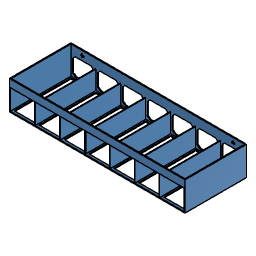
Small_Holder_PRINT (Autodesk Fusion 360 design; units mm, degrees)
Autodesk Fusion 360 part; units mm, degrees
sketch "Sketch1" plane through (0, 0, 0) normal (0, 0, 1) x (1, 0, 0)
  line L0 (0, 0) -> (232.6, 0)
  line L1 (232.6, 0) -> (232.6, 81.6)
  line L2 (232.6, 81.6) -> (0, 81.6)
  line L3 (0, 81.6) -> (0, 0)
  line L4 (1.2, 80.4) -> (231.4, 80.4)
  line L5 (231.4, 80.4) -> (231.4, 1.2)
  line L6 (231.4, 1.2) -> (1.2, 1.2)
  line L7 (1.2, 1.2) -> (1.2, 80.4)
  line L8 (3.2, 78.4) -> (31.4, 78.4)
  line L9 (31.4, 78.4) -> (31.4, 3.2)
  line L10 (31.4, 3.2) -> (3.2, 3.2)
  line L11 (3.2, 3.2) -> (3.2, 78.4)
  line L12 (33.4, 80.4) -> (34.2, 80.4)
  line L13 (34.2, 80.4) -> (34.2, 1.2)
  line L14 (34.2, 1.2) -> (33.4, 1.2)
  line L15 (33.4, 1.2) -> (33.4, 80.4)
  line L16 (36.2, 78.4) -> (64.4, 78.4)
  line L17 (36.2, 3.2) -> (36.2, 78.4)
  line L18 (64.4, 78.4) -> (64.4, 3.2)
  line L19 (64.4, 3.2) -> (36.2, 3.2)
  line L20 (69.2, 78.4) -> (97.4, 78.4)
  line L21 (69.2, 3.2) -> (69.2, 78.4)
  line L22 (97.4, 78.4) -> (97.4, 3.2)
  line L23 (97.4, 3.2) -> (69.2, 3.2)
  line L24 (102.2, 78.4) -> (130.4, 78.4)
  line L25 (102.2, 3.2) -> (102.2, 78.4)
  line L26 (130.4, 78.4) -> (130.4, 3.2)
  line L27 (130.4, 3.2) -> (102.2, 3.2)
  line L28 (135.2, 78.4) -> (163.4, 78.4)
  line L29 (135.2, 3.2) -> (135.2, 78.4)
  line L30 (163.4, 78.4) -> (163.4, 3.2)
  line L31 (163.4, 3.2) -> (135.2, 3.2)
  line L32 (168.2, 78.4) -> (196.4, 78.4)
  line L33 (168.2, 3.2) -> (168.2, 78.4)
  line L34 (196.4, 78.4) -> (196.4, 3.2)
  line L35 (196.4, 3.2) -> (168.2, 3.2)
  line L36 (66.4, 80.4) -> (67.2, 80.4)
  line L37 (67.2, 80.4) -> (67.2, 1.2)
  line L38 (67.2, 1.2) -> (66.4, 1.2)
  line L39 (66.4, 1.2) -> (66.4, 80.4)
  line L40 (99.4, 80.4) -> (100.2, 80.4)
  line L41 (100.2, 80.4) -> (100.2, 1.2032)
  line L42 (100.2, 1.2032) -> (99.4, 1.2032)
  line L43 (99.4, 1.2032) -> (99.4, 80.4)
  line L44 (132.4, 80.4) -> (133.2, 80.4)
  line L45 (133.2, 80.4) -> (133.2, 1.2)
  line L46 (133.2, 1.2) -> (132.4, 1.2)
  line L47 (132.4, 1.2) -> (132.4, 80.4)
  line L48 (165.4, 80.4) -> (166.2, 80.4)
  line L49 (166.2, 80.4) -> (166.2, 1.2)
  line L50 (166.2, 1.2) -> (165.4, 1.2)
  line L51 (165.4, 1.2) -> (165.4, 80.4)
  line L52 (198.4, 80.4) -> (199.2, 80.4)
  line L53 (199.2, 80.4) -> (199.2, 1.2)
  line L54 (199.2, 1.2) -> (198.4, 1.2)
  line L55 (198.4, 1.2) -> (198.4, 80.4)
  line L56 (201.2, 78.4) -> (229.4, 78.4)
  line L57 (201.2, 3.2) -> (201.2, 78.4)
  line L58 (229.4, 3.2) -> (201.2, 3.2)
  line L59 (229.4, 78.4) -> (229.4, 3.2)
  line L60 (231.4, 80.4) -> (232.2, 80.4)
  line L61 (232.2, 1.2) -> (231.4, 1.2)
  dimension "d1" = 1.2
  dimension "d2" = 1.2
  dimension "d3" = 1.2
  dimension "d4" = 1.2
  dimension "d5" = 2
  dimension "d6" = 2
  dimension "d7" = 2
  dimension "d8" = 81.6
  dimension "d9" = 0.8
  dimension "d10" = 2
  dimension "d11" = 32.2
  dimension "d12" = 0.8
  dimension "d13" = 0.8
  dimension "d14" = 0.8
  dimension "d15" = 0.8
  dimension "d16" = 2
  dimension "d17" = 0
  dimension "d19" = 2
  dimension "d21" = 32.2
  dimension "d22" = 2
  dimension "d23" = 2
  dimension "d24" = 32.2
  dimension "d25" = 2
  dimension "d26" = 2
  dimension "d27" = 32.2
  dimension "d28" = 2
  dimension "d29" = 2
  dimension "d30" = 32.2
  dimension "d31" = 2
  dimension "d32" = 0.8
  dimension "d33" = 2
  dimension "d34" = 32.2
  dimension "d35" = 2
  dimension "d36" = 2
  dimension "d38" = 2
  dimension "d39" = 2
  dimension "d40" = 2
  dimension "d41" = 2
  dimension "d43" = 2
  dimension "d47" = 2
  dimension "d48" = 2
  dimension "d49" = 2
  dimension "d50" = 2
  dimension "d51" = 2
  dimension "d52" = 2
  dimension "d53" = 32.2
  dimension "d54" = 1.2
  dimension "d306" = 0
  dimension "d307" = 0
  dimension "d308" = 0
  dimension "d309" = 0
  constraint horizontal L0
  constraint vertical L1
  constraint horizontal L2
  constraint vertical L3
  constraint coincident L0.start L3.end
  constraint horizontal L4
  constraint vertical L5
  constraint horizontal L6
  constraint vertical L7
  constraint horizontal L8
  constraint vertical L9
  constraint horizontal L10
  constraint vertical L11
  constraint horizontal L12
  constraint vertical L13
  constraint horizontal L14
  constraint vertical L15
  constraint coincident L6 L13.end
  constraint coincident L4 L12.start
  constraint horizontal L16
  constraint vertical L18
  constraint horizontal L19
  constraint vertical L17
  constraint horizontal L20
  constraint vertical L22
  constraint horizontal L23
  constraint vertical L21
  constraint horizontal L24
  constraint vertical L26
  constraint horizontal L27
  constraint vertical L25
  constraint horizontal L28
  constraint vertical L30
  constraint horizontal L31
  constraint vertical L29
  constraint horizontal L32
  constraint vertical L34
  constraint horizontal L35
  constraint vertical L33
  constraint horizontal L36
  constraint vertical L37
  constraint horizontal L38
  constraint vertical L39
  constraint coincident L4 L36.start
  constraint horizontal L40
  constraint vertical L41
  constraint horizontal L42
  constraint vertical L43
  constraint coincident L4 L40.start
  constraint horizontal L44
  constraint vertical L45
  constraint horizontal L46
  constraint vertical L47
  constraint coincident L4 L44.start
  constraint horizontal L48
  constraint vertical L49
  constraint horizontal L50
  constraint vertical L51
  constraint coincident L4 L48.start
  constraint horizontal L52
  constraint vertical L53
  constraint horizontal L54
  constraint vertical L55
  constraint coincident L4 L52.start
  constraint horizontal L56
  constraint vertical L59
  constraint horizontal L58
  constraint vertical L57
  constraint horizontal L60
  constraint horizontal L61
  constraint coincident L4 L5.start
  measures "d1" distance of L3 L7
  measures "d2" distance of L2 L4
  measures "d3" distance of L0 L6
  measures "d4" distance of L1 L5
  measures "d5" distance of L7 L11
  measures "d6" distance of L6 L10
  measures "d7" distance of L4 L8
  measures "d8" distance of L0.start L2.end
  measures "d9" distance of L13.end L14.end
  measures "d10" distance of L9 L15
  measures "d11" distance of L7 L15
  measures "d12" distance of L36.start L36.end
  measures "d13" distance of L40.start L40.end
  measures "d14" distance of L44.start L44.end
  measures "d15" distance of L48.start L48.end
  measures "d16" distance of L13 L17
  measures "d17" distance of L10 L19
  measures "d19" distance of L18 L39
  measures "d21" distance of L13 L39
  measures "d22" distance of L21 L37
  measures "d23" distance of L22 L43
  measures "d24" distance of L37 L43
  measures "d25" distance of L25 L41
  measures "d26" distance of L26 L47
  measures "d27" distance of L41 L47
  measures "d28" distance of L29 L45
  measures "d29" distance of L30 L51
  measures "d30" distance of L45 L51
  measures "d31" distance of L33 L49
  measures "d32" distance of L52.start L52.end
  measures "d33" distance of L34 L55
  measures "d34" distance of L49 L55
  measures "d35" distance of L4 L16
  measures "d36" distance of L4 L20
  measures "d38" distance of L4 L24
  measures "d39" distance of L4 L28
  measures "d40" distance of L4 L32
  measures "d41" distance of L53 L57
  measures "d43" distance of L4 L56
  measures "d47" distance of L6 L58
  measures "d48" distance of L6 L35
  measures "d49" distance of L6 L31
  measures "d50" distance of L6 L27
  measures "d51" distance of L6 L23
  measures "d52" distance of L5 L59
  measures "d53" distance of L5 L53
  measures "d54" distance of L2 L4
extrude "Extrude2" add sketch "Sketch1" along normal blind 38.2 contours L0 L1 L2 L3
extrude "Extrude1" add sketch "Sketch1" along normal blind 38 contours L4 L6 L7 L15 | L4 L6 L12 L13 L14 L15 | L4 L6 L13 L39 | L4 L6 L36 L37 L38 L39 | L4 L6 L37 L41 L42 L43 L47 | L4 L40 L41 L42 L43 | L4 L6 L44 L45 L46 L47 | L4 L6 L45 L51 | L4 L6 L48 L49 L50 L51 | L4 L6 L49 L55 | L4 L6 L52 L53 L54 L55 | L4 L5 L6 L53 | L8 L9 L10 L11 | L16 L17 L18 L19 | L20 L21 L22 L23 | L24 L25 L26 L27 | L28 L29 L30 L31 | L32 L33 L34 L35 | L56 L57 L58 L59
extrude "Extrude3" cut sketch "Sketch1" along normal blind 38 contours L8 L9 L10 L11 | L16 L17 L18 L19 | L20 L21 L22 L23 | L24 L25 L26 L27 | L28 L29 L30 L31 | L32 L33 L34 L35 | L56 L57 L58 L59
extrude "Extrude4" cut sketch "Sketch1" against normal blind 36.8 from surface at 38 contours L4 L6 L7 L15 | L4 L6 L13 L39 | L4 L6 L37 L41 L42 L43 L47 | L4 L6 L45 L51 | L4 L6 L49 L55 | L4 L5 L6 L53
sketch "Sketch2" plane through (0, 0, 0) normal (0, -1, 0) x (1, 0, 0)
  line L0 (0, 0) -> (232.6, 0)
  line L1 (232.6, 0) -> (232.6, 38.2)
  line L2 (232.6, 38.2) -> (0, 38.2)
  line L3 (0, 38.2) -> (0, 0)
  line L4 (1.2, 28.2) -> (33.4, 28.2)
  line L5 (33.4, 28.2) -> (33.4, 1.2)
  line L6 (33.4, 1.2) -> (1.2, 1.2)
  line L7 (1.2, 1.2) -> (1.2, 28.2)
  line L8 (34.2, 28.2) -> (66.4, 28.2)
  line L9 (66.4, 28.2) -> (66.4, 1.2)
  line L10 (66.4, 1.2) -> (34.2, 1.2)
  line L11 (34.2, 1.2) -> (34.2, 28.2)
  line L12 (67.2, 28.2) -> (99.4, 28.2)
  line L13 (99.4, 28.2) -> (99.4, 1.2)
  line L14 (99.4, 1.2) -> (67.2, 1.2)
  line L15 (67.2, 1.2) -> (67.2, 28.2)
  line L16 (100.2, 28.2) -> (132.4, 28.2)
  line L17 (132.4, 28.2) -> (132.4, 1.2)
  line L18 (132.4, 1.2) -> (100.2, 1.2)
  line L19 (100.2, 1.2) -> (100.2, 28.2)
  line L20 (133.2, 28.2) -> (165.4, 28.2)
  line L21 (165.4, 28.2) -> (165.4, 1.2)
  line L22 (165.4, 1.2) -> (133.2, 1.2)
  line L23 (133.2, 1.2) -> (133.2, 28.2)
  line L24 (1.2, 1.2) -> (1.2, 38.2)
  line L25 (166.2, 28.2) -> (198.4, 28.2)
  line L26 (166.2, 1.2) -> (166.2, 28.2)
  line L27 (198.4, 1.2) -> (166.2, 1.2)
  line L28 (198.4, 28.2) -> (198.4, 1.2)
  line L29 (199.2, 28.2) -> (231.4, 28.2)
  line L30 (199.2, 1.2) -> (199.2, 28.2)
  line L31 (231.4, 1.2) -> (199.2, 1.2)
  line L32 (231.4, 28.2) -> (231.4, 1.2)
  dimension "d65" = 32.2
  dimension "d66" = 0.8
  dimension "d67" = 32.2
  dimension "d68" = 0.8
  dimension "d69" = 32.2
  dimension "d70" = 0.8
  dimension "d71" = 32.2
  dimension "d72" = 0.8
  dimension "d73" = 32.2
  dimension "d74" = 32.2
  dimension "d75" = 32.2
  dimension "d77" = 0.8
  dimension "d78" = 0.8
  dimension "d79" = 1.2
  dimension "d80" = 27
  dimension "d81" = 27
  dimension "d82" = 27
  dimension "d83" = 10
  dimension "d84" = 10
  dimension "d85" = 10
  dimension "d86" = 10
  dimension "d87" = 10
  dimension "d88" = 10
  dimension "d89" = 10
  dimension "d90" = 9.8
  dimension "d91" = 27
  dimension "d92" = 27
  dimension "d93" = 27
  dimension "d94" = 27
  constraint horizontal L4
  constraint vertical L5
  constraint horizontal L6
  constraint vertical L7
  constraint horizontal L8
  constraint vertical L9
  constraint horizontal L10
  constraint vertical L11
  constraint horizontal L12
  constraint vertical L13
  constraint horizontal L14
  constraint vertical L15
  constraint horizontal L16
  constraint vertical L17
  constraint horizontal L18
  constraint vertical L19
  constraint horizontal L20
  constraint vertical L21
  constraint horizontal L22
  constraint vertical L23
  constraint collinear L7 L24
  constraint horizontal L25
  constraint vertical L28
  constraint horizontal L27
  constraint vertical L26
  constraint horizontal L29
  constraint vertical L32
  constraint horizontal L31
  constraint vertical L30
  measures "d65" distance of L4.start L4.end
  measures "d66" distance of L5 L11
  measures "d67" distance of L9.end L10.end
  measures "d68" distance of L9 L15
  measures "d69" distance of L13.end L14.end
  measures "d70" distance of L13 L19
  measures "d71" distance of L17.end L18.end
  measures "d72" distance of L17 L23
  measures "d73" distance of L21.end L22.end
  measures "d74" distance of L26.start L27.start
  measures "d75" distance of L30.start L31.start
  measures "d77" distance of L21 L26
  measures "d78" distance of L28 L30
  measures "d79" distance of L1 L32
  measures "d80" distance of L4.start L6.end
  measures "d81" distance of L8.start L10.end
  measures "d82" distance of L12.start L14.end
  measures "d83" distance of L2 L4
  measures "d84" distance of L2 L8
  measures "d85" distance of L2 L12
  measures "d86" distance of L2 L16
  measures "d87" distance of L2 L20
  measures "d88" distance of L2 L25
  measures "d89" distance of L2 L29
  measures "d91" distance of L29.end L31.start
  measures "d92" distance of L25.end L27.start
  measures "d93" distance of L20.end L21.end
  measures "d94" distance of L16.end L17.end
extrude "Extrude5" cut sketch "Sketch2" against normal blind 1.2 contours L4 L5 L6 L7 L24 | L8 L9 L10 L11 | L12 L13 L14 L15 | L16 L17 L18 L19 | L20 L21 L22 L23 | L25 L26 L27 L28 | L29 L30 L31 L32
sketch "Sketch3" plane through (0, 80.4, 0) normal (0, -1, 0) x (1, 0, 0)
  line L0 (231.4, 1.2) -> (231.4, 38.2)
  line L1 (231.4, 38.2) -> (1.2, 38.2)
  line L2 (1.2, 38.2) -> (1.2, 1.2)
  line L3 (3.2, 6.3232) -> (7.1045, 3.2)
  line L4 (7.1045, 3.2) -> (27.8654, 3.2)
  line L5 (27.8654, 3.2) -> (31.4, 6.7364)
  line L6 (31.4, 22.6654) -> (31.4, 6.7364)
  line L7 (31.4, 22.6654) -> (27.8636, 26.2)
  line L8 (6.7346, 26.2) -> (27.8636, 26.2)
  line L9 (6.7346, 26.2) -> (3.2, 22.6636)
  line L10 (3.2, 22.6636) -> (3.2, 6.3232)
  line L11 (1.2, 28.2) -> (33.4, 28.2)
  line L12 (33.4, 28.2) -> (33.4, 1.2)
  line L13 (33.4, 1.2) -> (1.2, 1.2)
  line L14 (39.7352, 26.2) -> (60.8766, 26.2)
  line L15 (36.2, 22.6641) -> (36.2, 6.3232)
  line L16 (39.7352, 26.2) -> (36.2, 22.6641)
  line L17 (36.2, 6.3232) -> (40.1046, 3.2)
  line L18 (40.1046, 3.2) -> (60.8772, 3.2)
  line L19 (60.8772, 3.2) -> (64.4124, 6.7359)
  line L20 (64.4124, 22.6648) -> (64.4124, 6.7359)
  line L21 (64.4124, 22.6648) -> (60.8766, 26.2)
  line L22 (72.7347, 26.2) -> (93.8636, 26.2)
  line L23 (69.2, 22.6636) -> (69.2, 6.3232)
  line L24 (72.7347, 26.2) -> (69.2, 22.6636)
  line L25 (69.2, 6.3232) -> (73.1046, 3.2)
  line L26 (73.1046, 3.2) -> (93.8653, 3.2)
  line L27 (93.8653, 3.2) -> (97.4, 6.7364)
  line L28 (97.4, 22.6653) -> (97.4, 6.7364)
  line L29 (97.4, 22.6653) -> (93.8636, 26.2)
  line L30 (105.7347, 26.2) -> (126.8636, 26.2)
  line L31 (102.2, 22.6636) -> (102.2, 6.3232)
  line L32 (105.7347, 26.2) -> (102.2, 22.6636)
  line L33 (102.2, 6.3232) -> (106.1046, 3.2)
  line L34 (106.1046, 3.2) -> (126.8653, 3.2)
  line L35 (126.8653, 3.2) -> (130.4, 6.7364)
  line L36 (130.4, 22.6653) -> (130.4, 6.7364)
  line L37 (130.4, 22.6653) -> (126.8636, 26.2)
  line L38 (138.7347, 26.2) -> (159.8636, 26.2)
  line L39 (135.2, 22.6636) -> (135.2, 6.3232)
  line L40 (138.7347, 26.2) -> (135.2, 22.6636)
  line L41 (135.2, 6.3232) -> (139.1046, 3.2)
  line L42 (139.1046, 3.2) -> (159.8653, 3.2)
  line L43 (159.8653, 3.2) -> (163.4, 6.7364)
  line L44 (163.4, 22.6653) -> (163.4, 6.7364)
  line L45 (163.4, 22.6653) -> (159.8636, 26.2)
  line L46 (204.7347, 26.2) -> (225.8636, 26.2)
  line L47 (201.2, 22.6636) -> (201.2, 6.3232)
  line L48 (204.7347, 26.2) -> (201.2, 22.6636)
  line L49 (201.2, 6.3232) -> (205.1046, 3.2)
  line L50 (205.1046, 3.2) -> (225.8653, 3.2)
  line L51 (225.8653, 3.2) -> (229.4, 6.7364)
  line L52 (229.4, 22.6653) -> (229.4, 6.7364)
  line L53 (229.4, 22.6653) -> (225.8636, 26.2)
  line L54 (199.2, 1.2) -> (199.2, 28.2)
  line L55 (199.2, 28.2) -> (231.4, 28.2)
  line L56 (231.4, 1.2) -> (199.2, 1.2)
  line L57 (198.4, 28.2) -> (198.4, 1.2)
  line L58 (133.2, 28.2) -> (165.4, 28.2)
  line L59 (165.4, 28.2) -> (165.4, 1.2)
  line L60 (165.4, 1.2) -> (133.2, 1.2)
  line L61 (133.2, 1.2) -> (133.2, 28.2)
  line L62 (132.4, 28.2) -> (132.4, 1.2)
  line L63 (132.4, 1.2) -> (100.2, 1.2)
  line L64 (100.2, 28.2) -> (132.4, 28.2)
  line L65 (100.2, 1.2) -> (100.2, 28.2)
  line L66 (67.2, 28.2) -> (99.4, 28.2)
  line L67 (99.4, 28.2) -> (99.4, 1.2)
  line L68 (99.4, 1.2) -> (67.2, 1.2)
  line L69 (67.2, 1.2) -> (67.2, 28.2)
  line L70 (34.2, 28.2) -> (66.4, 28.2)
  line L71 (34.2, 1.2) -> (34.2, 28.2)
  line L72 (66.4, 1.2) -> (34.2, 1.2)
  line L73 (171.7347, 26.2) -> (192.8636, 26.2)
  line L74 (168.2, 22.6636) -> (168.2, 6.3232)
  line L75 (171.7347, 26.2) -> (168.2, 22.6636)
  line L76 (168.2, 6.3232) -> (172.1046, 3.2)
  line L77 (172.1046, 3.2) -> (192.8653, 3.2)
  line L78 (192.8653, 3.2) -> (196.4, 6.7364)
  line L79 (196.4, 22.6653) -> (196.4, 6.7364)
  line L80 (196.4, 22.6653) -> (192.8636, 26.2)
  line L81 (166.2, 1.2) -> (166.2, 28.2)
  line L82 (198.4, 1.2) -> (166.2, 1.2)
  line L83 (166.2, 28.2) -> (198.4, 28.2)
  line L84 (33.4, 38) -> (34.2, 38)
  line L85 (34.2, 38) -> (34.2, 1.2)
  line L86 (34.2, 1.2) -> (66.4, 1.2)
  line L87 (66.4, 1.2) -> (66.4, 38)
  line L88 (66.4, 38) -> (67.2, 38)
  line L89 (67.2, 38) -> (67.2, 1.2)
  line L90 (67.2, 1.2) -> (99.4, 1.2)
  line L91 (99.4, 1.2) -> (99.4, 38)
  line L92 (99.4, 38) -> (100.2, 38)
  line L93 (100.2, 38) -> (100.2, 1.2)
  line L94 (100.2, 1.2) -> (132.4, 1.2)
  line L95 (132.4, 1.2) -> (132.4, 38)
  line L96 (132.4, 38) -> (133.2, 38)
  line L97 (133.2, 38) -> (133.2, 1.2)
  line L98 (133.2, 1.2) -> (165.4, 1.2)
  line L99 (165.4, 1.2) -> (165.4, 38)
  line L100 (165.4, 38) -> (166.2, 38)
  line L101 (166.2, 38) -> (166.2, 1.2)
  line L102 (166.2, 1.2) -> (198.4, 1.2)
  line L103 (198.4, 1.2) -> (198.4, 38)
  line L104 (198.4, 38) -> (199.2, 38)
  line L105 (199.2, 38) -> (199.2, 1.2)
  line L106 (199.2, 1.2) -> (231.4, 1.2)
  line L107 (1.2, 1.2) -> (33.4, 1.2)
  line L108 (33.4, 1.2) -> (33.4, 38)
  dimension "d97" = 5
  dimension "d98" = 5
  dimension "d99" = 5
  dimension "d100" = 5
  dimension "d101" = 2
  dimension "d102" = 2
  dimension "d103" = 2
  dimension "d105" = 2
  dimension "d106" = 5
  dimension "d107" = 5
  dimension "d108" = 5
  dimension "d109" = 5
  dimension "d110" = 5
  dimension "d111" = 5
  dimension "d112" = 5
  dimension "d113" = 5
  dimension "d114" = 5
  dimension "d115" = 5
  dimension "d116" = 5
  dimension "d117" = 5
  dimension "d118" = 5
  dimension "d119" = 5
  dimension "d120" = 5
  dimension "d121" = 5
  dimension "d126" = 5
  dimension "d127" = 5
  dimension "d128" = 5
  dimension "d129" = 5
  dimension "d130" = 2
  dimension "d131" = 2
  dimension "d132" = 2
  dimension "d133" = 2
  dimension "d135" = 2
  dimension "d136" = 2
  dimension "d137" = 2
  dimension "d138" = 2
  dimension "d139" = 2
  dimension "d140" = 2
  dimension "d141" = 2
  dimension "d142" = 2
  dimension "d143" = 2
  dimension "d145" = 2
  dimension "d146" = 2
  dimension "d147" = 2
  dimension "d148" = 2
  dimension "d149" = 2
  dimension "d150" = 2
  dimension "d151" = 5
  dimension "d152" = 5
  dimension "d153" = 5
  dimension "d154" = 5
  dimension "d155" = 2
  dimension "d156" = 2
  dimension "d157" = 2
  dimension "d158" = 2
  constraint perpendicular L4 L6
  constraint perpendicular L5 L7
  constraint perpendicular L6 L8
  constraint perpendicular L7 L9
  constraint parallel L2 L10
  constraint perpendicular L18 L20
  constraint perpendicular L19 L21
  constraint perpendicular L14 L20
  constraint perpendicular L16 L21
  constraint perpendicular L26 L28
  constraint perpendicular L27 L29
  constraint perpendicular L22 L28
  constraint perpendicular L24 L29
  constraint perpendicular L34 L36
  constraint perpendicular L35 L37
  constraint perpendicular L30 L36
  constraint perpendicular L32 L37
  constraint perpendicular L42 L44
  constraint perpendicular L43 L45
  constraint perpendicular L38 L44
  constraint perpendicular L40 L45
  constraint perpendicular L50 L52
  constraint perpendicular L51 L53
  constraint perpendicular L46 L52
  constraint perpendicular L48 L53
  constraint perpendicular L77 L79
  constraint perpendicular L78 L80
  constraint perpendicular L73 L79
  constraint perpendicular L75 L80
  measures "d97" distance of L8.start L9.end
  measures "d98" distance of L6.start L7.end
  measures "d99" distance of L3.start L3.end
  measures "d100" distance of L4.end L5.end
  measures "d101" distance of L8 L11
  measures "d102" distance of L2 L10
  measures "d103" distance of L6 L12
  measures "d105" distance of L4 L13
  measures "d106" distance of L15.start L14.start
  measures "d107" distance of L20.start L14.end
  measures "d108" distance of L15.end L17.end
  measures "d109" distance of L19.end L18.end
  measures "d110" distance of L23.start L22.start
  measures "d111" distance of L28.start L22.end
  measures "d112" distance of L23.end L25.end
  measures "d113" distance of L27.end L26.end
  measures "d114" distance of L31.start L30.start
  measures "d115" distance of L36.start L30.end
  measures "d116" distance of L31.end L33.end
  measures "d117" distance of L35.end L34.end
  measures "d118" distance of L39.start L38.start
  measures "d119" distance of L44.start L38.end
  measures "d120" distance of L39.end L41.end
  measures "d121" distance of L43.end L42.end
  measures "d126" distance of L47.start L46.start
  measures "d127" distance of L52.start L46.end
  measures "d128" distance of L47.end L49.end
  measures "d129" distance of L51.end L50.end
  measures "d130" distance of L47 L54
  measures "d131" distance of L0 L52
  measures "d132" distance of L46 L55
  measures "d133" distance of L50 L56
  measures "d135" distance of L38 L58
  measures "d136" distance of L44 L59
  measures "d137" distance of L42 L60
  measures "d138" distance of L39 L61
  measures "d139" distance of L36 L62
  measures "d140" distance of L34 L63
  measures "d141" distance of L30 L64
  measures "d142" distance of L31 L65
  measures "d143" distance of L22 L66
  measures "d145" distance of L28 L67
  measures "d146" distance of L26 L68
  measures "d147" distance of L23 L69
  measures "d148" distance of L14 L70
  measures "d149" distance of L15 L71
  measures "d150" distance of L18 L72
  measures "d151" distance of L74.start L73.start
  measures "d152" distance of L79.start L73.end
  measures "d153" distance of L74.end L76.end
  measures "d154" distance of L78.end L77.end
  measures "d155" distance of L74 L81
  measures "d156" distance of L57 L79
  measures "d157" distance of L77 L82
  measures "d158" distance of L73 L83
extrude "Extrude6" cut sketch "Sketch3" against normal blind 1.2 contours L3 L4 L5 L6 L7 L8 L9 L10 | L14 L15 L16 L17 L18 L19 L20 L21 | L22 L23 L24 L25 L26 L27 L28 L29 | L30 L31 L32 L33 L34 L35 L36 L37 | L38 L39 L40 L41 L42 L43 L44 L45 | L46 L47 L48 L49 L50 L51 L52 L53 | L73 L74 L75 L76 L77 L78 L79 L80
sketch "Sketch4" plane through (33.4, 0, 0) normal (-1, 0, 0) x (0, -1, 0)
  line L0 (-1.2, 38) -> (-80.4, 38)
  line L1 (-1.2, 38) -> (-13.2, 26)
  line L2 (-1.2, 38) -> (16.4477, 38) construction
  line L3 (-13.2, 26) -> (-80.4, 26)
  line L4 (-80.4, 26) -> (-80.4, 38)
  line L5 (-80.4, 38) -> (-1.2, 38)
  line L6 (-80.4, 38) -> (-80.4, 1.2)
  line L7 (-80.4, 1.2) -> (0, 1.2)
  line L8 (0, 1.2) -> (0, 28.2)
  line L9 (0, 28.2) -> (-1.2, 28.2)
  line L10 (-1.2, 28.2) -> (-1.2, 38)
  dimension "d161" = 135
  dimension "d162" = 12
  constraint horizontal L2
  constraint coincident L0.start L1.start
  constraint coincident L0.end L4.end
  measures "d161" angle of L1 L2
  measures "d162" distance of L3 L5
extrude "Extrude7" cut sketch "Sketch4" against normal blind 165.8 contours L0 L1 L3 L4 L5 L6
sketch "Sketch5" plane through (0, 80.4, 0) normal (0, -1, 0) x (1, 0, 0)
  line L0 (69.2, 6.3232) -> (69.2, 22.6636)
  line L1 (69.2, 22.6636) -> (72.7347, 26.2)
  line L2 (72.7347, 26.2) -> (93.8636, 26.2)
  line L3 (93.8636, 26.2) -> (97.4, 22.6653)
  line L4 (97.4, 22.6653) -> (97.4, 6.7364)
  line L5 (97.4, 6.7364) -> (93.8653, 3.2)
  line L6 (93.8653, 3.2) -> (73.1046, 3.2)
  line L7 (73.1046, 3.2) -> (69.2, 6.3232)
  line L8 (201.2, 6.3232) -> (201.2, 22.6636)
  line L9 (201.2, 22.6636) -> (204.7347, 26.2)
  line L10 (204.7347, 26.2) -> (225.8636, 26.2)
  line L11 (225.8636, 26.2) -> (229.4, 22.6653)
  line L12 (229.4, 22.6653) -> (229.4, 6.7364)
  line L13 (229.4, 6.7364) -> (225.8653, 3.2)
  line L14 (225.8653, 3.2) -> (205.1046, 3.2)
  line L15 (205.1046, 3.2) -> (201.2, 6.3232)
  line L16 (102.2, 6.3232) -> (102.2, 22.6636)
  line L17 (102.2, 22.6636) -> (105.7347, 26.2)
  line L18 (105.7347, 26.2) -> (126.8636, 26.2)
  line L19 (126.8636, 26.2) -> (130.4, 22.6653)
  line L20 (130.4, 22.6653) -> (130.4, 6.7364)
  line L21 (130.4, 6.7364) -> (126.8653, 3.2)
  line L22 (126.8653, 3.2) -> (106.1046, 3.2)
  line L23 (106.1046, 3.2) -> (102.2, 6.3232)
  line L24 (36.2, 6.3232) -> (36.2, 22.6641)
  line L25 (36.2, 22.6641) -> (39.7352, 26.2)
  line L26 (39.7352, 26.2) -> (60.8766, 26.2)
  line L27 (60.8766, 26.2) -> (64.4124, 22.6648)
  line L28 (64.4124, 22.6648) -> (64.4124, 6.7359)
  line L29 (64.4124, 6.7359) -> (60.8772, 3.2)
  line L30 (60.8772, 3.2) -> (40.1046, 3.2)
  line L31 (40.1046, 3.2) -> (36.2, 6.3232)
  line L32 (168.2, 6.3232) -> (168.2, 22.6636)
  line L33 (168.2, 22.6636) -> (171.7347, 26.2)
  line L34 (171.7347, 26.2) -> (192.8636, 26.2)
  line L35 (192.8636, 26.2) -> (196.4, 22.6653)
  line L36 (196.4, 22.6653) -> (196.4, 6.7364)
  line L37 (196.4, 6.7364) -> (192.8653, 3.2)
  line L38 (192.8653, 3.2) -> (172.1046, 3.2)
  line L39 (172.1046, 3.2) -> (168.2, 6.3232)
  line L40 (135.2, 6.3232) -> (135.2, 22.6636)
  line L41 (135.2, 22.6636) -> (138.7347, 26.2)
  line L42 (138.7347, 26.2) -> (159.8636, 26.2)
  line L43 (159.8636, 26.2) -> (163.4, 22.6653)
  line L44 (163.4, 22.6653) -> (163.4, 6.7364)
  line L45 (163.4, 6.7364) -> (159.8653, 3.2)
  line L46 (159.8653, 3.2) -> (139.1046, 3.2)
  line L47 (139.1046, 3.2) -> (135.2, 6.3232)
  line L48 (3.2, 6.3232) -> (3.2, 22.6636)
  line L49 (3.2, 22.6636) -> (6.7346, 26.2)
  line L50 (6.7346, 26.2) -> (27.8636, 26.2)
  line L51 (27.8636, 26.2) -> (31.4, 22.6654)
  line L52 (31.4, 22.6654) -> (31.4, 6.7364)
  line L53 (31.4, 6.7364) -> (27.8654, 3.2)
  line L54 (27.8654, 3.2) -> (7.1045, 3.2)
  line L55 (7.1045, 3.2) -> (3.2, 6.3232)
  line L56 (231.4, 1.2) -> (231.4, 38.2)
  line L57 (231.4, 38.2) -> (1.2, 38.2)
  line L58 (1.2, 38.2) -> (1.2, 1.2)
  circle A0 centre (216.3, 32.2) radius 2
  circle A1 centre (16.3, 32.2) radius 2
  line L59 (199.2, 26) -> (199.2, 1.2)
  line L60 (199.2, 1.2) -> (231.4, 1.2)
  line L61 (1.2, 1.2) -> (33.4, 1.2)
  line L62 (33.4, 1.2) -> (33.4, 26)
  line L63 (33.4, 26) -> (34.2, 26)
  line L64 (34.2, 26) -> (34.2, 1.2)
  line L65 (34.2, 1.2) -> (66.4, 1.2)
  line L66 (66.4, 1.2) -> (66.4, 26)
  line L67 (66.4, 26) -> (67.2, 26)
  line L68 (67.2, 26) -> (67.2, 1.2)
  line L69 (67.2, 1.2) -> (99.4, 1.2)
  line L70 (99.4, 1.2) -> (99.4, 26)
  line L71 (99.4, 26) -> (100.2, 26)
  line L72 (100.2, 26) -> (100.2, 1.2)
  line L73 (100.2, 1.2) -> (132.4, 1.2)
  line L74 (132.4, 1.2) -> (132.4, 26)
  line L75 (132.4, 26) -> (133.2, 26)
  line L76 (133.2, 26) -> (133.2, 1.2)
  line L77 (133.2, 1.2) -> (165.4, 1.2)
  line L78 (165.4, 1.2) -> (165.4, 26)
  line L79 (165.4, 26) -> (166.2, 26)
  line L80 (166.2, 26) -> (166.2, 1.2)
  line L81 (166.2, 1.2) -> (198.4, 1.2)
  line L82 (198.4, 1.2) -> (198.4, 26)
  line L83 (198.4, 26) -> (199.2, 26)
  dimension "d165" = 4
  dimension "d166" = 4
  dimension "d167" = 15.1
  dimension "d168" = 6
  dimension "d169" = 15.1
  dimension "d170" = 6
  measures "d165" diameter of A0
  measures "d166" diameter of A1
  measures "d167" distance of L58 A1.centre
  measures "d168" distance of L57 A1.centre
  measures "d169" distance of L56 A0.centre
  measures "d170" distance of L57 A0.centre
extrude "Extrude8" cut sketch "Sketch5" against normal blind 1.2 contours A0 | A1
sketch "Sketch6" plane through (0, 0, 0) normal (0, -1, 0) x (1, 0, 0)
  line L0 (99.4, 28.2) -> (99.4, 1.2)
  line L1 (99.4, 1.2) -> (67.2, 1.2)
  line L2 (67.2, 1.2) -> (67.2, 28.2)
  line L3 (67.2, 28.2) -> (99.4, 28.2)
  line L4 (199.2, 1.2) -> (199.2, 28.2)
  line L5 (199.2, 28.2) -> (231.4, 28.2)
  line L6 (231.4, 28.2) -> (231.4, 1.2)
  line L7 (231.4, 1.2) -> (199.2, 1.2)
  line L8 (132.4, 28.2) -> (132.4, 1.2)
  line L9 (132.4, 1.2) -> (100.2, 1.2)
  line L10 (100.2, 1.2) -> (100.2, 28.2)
  line L11 (100.2, 28.2) -> (132.4, 28.2)
  line L12 (66.4, 28.2) -> (66.4, 1.2)
  line L13 (66.4, 1.2) -> (34.2, 1.2)
  line L14 (34.2, 1.2) -> (34.2, 28.2)
  line L15 (34.2, 28.2) -> (66.4, 28.2)
  line L16 (166.2, 1.2) -> (166.2, 28.2)
  line L17 (166.2, 28.2) -> (198.4, 28.2)
  line L18 (198.4, 28.2) -> (198.4, 1.2)
  line L19 (198.4, 1.2) -> (166.2, 1.2)
  line L20 (165.4, 28.2) -> (165.4, 1.2)
  line L21 (165.4, 1.2) -> (133.2, 1.2)
  line L22 (133.2, 1.2) -> (133.2, 28.2)
  line L23 (133.2, 28.2) -> (165.4, 28.2)
  line L24 (33.4, 28.2) -> (33.4, 1.2)
  line L25 (33.4, 1.2) -> (1.2, 1.2)
  line L26 (1.2, 1.2) -> (1.2, 28.2)
  line L27 (1.2, 28.2) -> (33.4, 28.2)
  line L28 (0, 0) -> (232.6, 0)
  line L29 (232.6, 0) -> (232.6, 38.2)
  line L30 (232.6, 38.2) -> (0, 38.2)
  line L31 (0, 38.2) -> (0, 0)
  line L32 (0, 38.2) -> (232.6, 38.2)
  line L33 (232.6, 38.2) -> (232.6, 28.2)
  line L34 (232.6, 28.2) -> (0, 28.2)
  line L35 (0, 28.2) -> (0, 38.2)
  dimension "d269" = 10
  constraint horizontal L32
  constraint vertical L33
  constraint horizontal L34
  constraint vertical L35
  constraint coincident L30.end L31.start
  measures "d269" distance of L30.end L34.end
